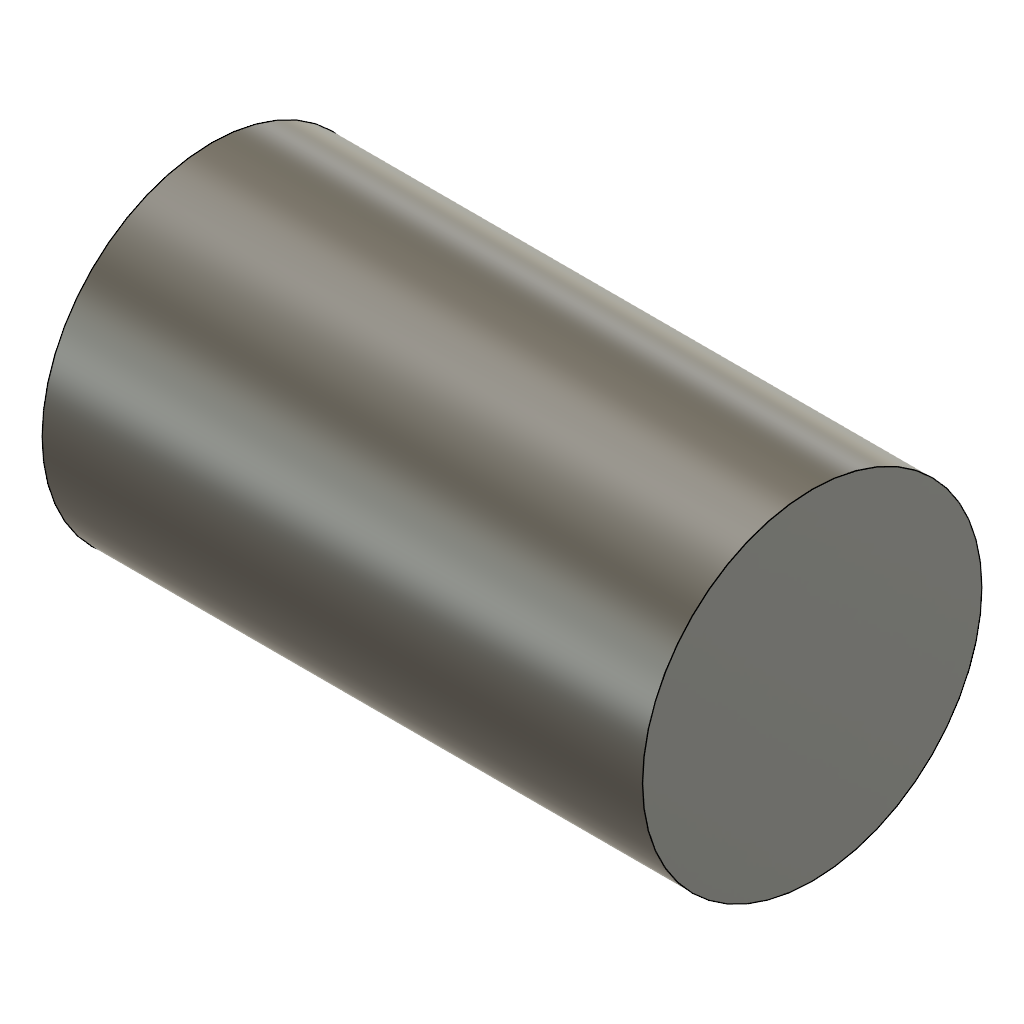
wide_frame_yz_edit_offset (Autodesk Fusion 360 design; units mm, degrees)
part number: 2026-11-27-17-36-48-145
Autodesk Fusion 360 part; units mm, degrees
sketch "CircularProfile" plane through (0, 0, 0) normal (1, 0, 0) x (0, 0, -1)
  circle A0 centre (13, -7) radius 13
extrude "OffsetTwoSides" add sketch "CircularProfile" along normal blind 17 and the other way blind 29 from surface at 10
